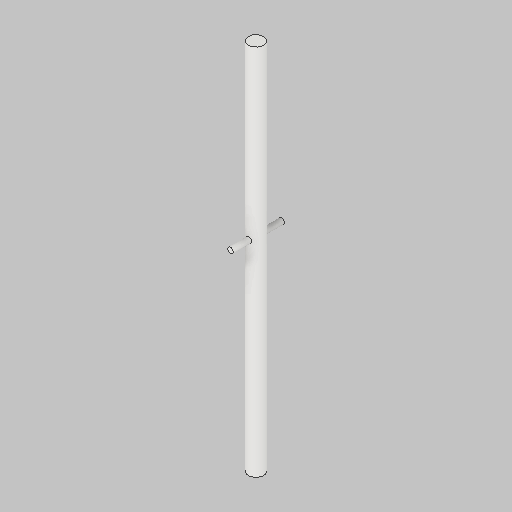
# Autodesk Inventor part: Straw
Saved by Autodesk Inventor 2026.1 (Build 301233000, 233)
## iProperties
Created: 2026-11-04
Part Number: Straw
Material: Generic
Document SubType Name: Modeling
Designer: FerdiaComerford
Density: 1 g/cm^3
Appearance: Default
Author: FerdiaComerford
Revision Number: 0
Autodesk Inventor part; units mm, degrees
ref_plane "YZ Plane" through (0, 0, 0) normal (1, 0, 0) x (0, 1, 0)
ref_plane "XZ Plane" through (0, 0, 0) normal (0, 1, 0) x (-1, 0, 0)
ref_plane "XY Plane" through (0, 0, 0) normal (0, 0, 1) x (1, 0, 0)
sketch "Sketch7" plane through (0, 0, 0) normal (0, 1, 0) x (-1, 0, 0)
  circle A0 centre (0, 0) radius 3
  dimension "d12" = 6
  constraints: 1 centre point, 1 coincident
  measures "d12" diameter of A0
extrude "Extrusion3" add sketch "Sketch7" along normal blind 146.25
sketch "Sketch8" plane through (0, 0, 0) normal (0, 0, 1) x (1, 0, 0)
  circle A0 centre (0, 80) radius 1.125
  line L0 (3, 0) -> (-3, 0) projected
  point P0 (0, 0)
  dimension "d15" = 2.25
  dimension "d16" = 80
  constraints: 1 centre point
  measures "d15" diameter of A0
  measures "d16" distance from line of L0 A0.centre
extrude "Extrusion4" add sketch "Sketch8" along normal blind 10 and the other way blind 10
body "Solid3"
